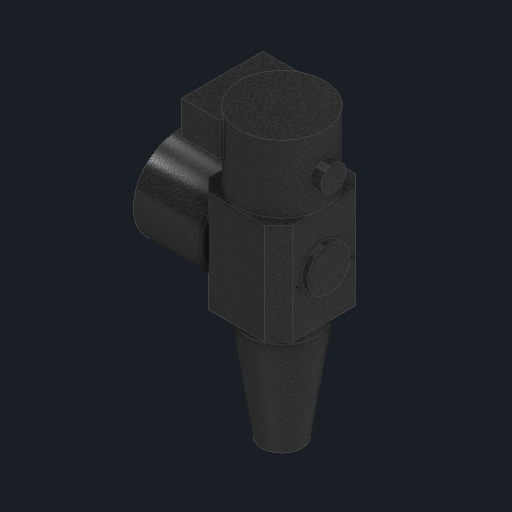
# Autodesk Inventor part: dec_housing
Saved by Autodesk Inventor 2027.1 (Build 311270010, 270A)
## iProperties
Created: 2026-11-03
Part Number: dec_housing
Material: Generic
Description: CG-5 RA shaft collar + Dec axis housing + counterweight cone (estimated)
Document SubType Name: Modeling
Designer: Claude (from photos)
Density: 1 g/cm^3
Appearance: Black Cast
Author: alexg
Autodesk Inventor part; units mm, degrees
ref_plane "Work Plane1" through (95, 0, 0) normal (1, 0, 0) x (0, 1, 0)
sketch "RA collar sketch" plane through (95, 0, 0) normal (1, 0, 0) x (0, 1, 0)
  circle A0 centre (0, 0) radius 40
  constraints: 1 centre point
extrude "RA collar" add sketch "RA collar sketch" along normal blind 60
ref_plane "Work Plane2" through (0, -45, 0) normal (0, 1, 0) x (-1, 0, 0)
sketch "Dec junction sketch" plane through (0, -45, 0) normal (0, 1, 0) x (-1, 0, 0)
  line L0 (-162, -40) -> (-212, -40)
  line L1 (-212, -40) -> (-224, -28)
  line L2 (-224, -28) -> (-224, 28)
  line L3 (-224, 28) -> (-212, 40)
  line L4 (-212, 40) -> (-162, 40)
  line L5 (-162, 40) -> (-150, 28)
  line L6 (-150, 28) -> (-150, -28)
  line L7 (-150, -28) -> (-162, -40)
  constraints: 16 end point
extrude "Dec junction" add sketch "Dec junction sketch" along normal blind 90
ref_plane "Work Plane3" through (0, 45, 0) normal (0, 1, 0) x (-1, 0, 0)
sketch "Dec housing sketch" plane through (0, 45, 0) normal (0, 1, 0) x (-1, 0, 0)
  circle A0 centre (-187, 0) radius 38
  constraints: 1 centre point
extrude "Dec housing" add sketch "Dec housing sketch" along normal blind 60
ref_plane "Work Plane4" through (0, -45, 0) normal (0, 1, 0) x (-1, 0, 0)
sketch "Dec circle seat sketch" plane through (0, -45, 0) normal (0, 1, 0) x (-1, 0, 0)
  circle A0 centre (-187, 0) radius 31
  constraints: 1 centre point
extrude "Dec circle seat" add sketch "Dec circle seat sketch" against normal blind 12
sketch "Counterweight cone sketch" plane through (0, 0, 0) normal (0, 0, 1) x (1, 0, 0)
  line L0 (187, -57) -> (187, -150)
  line L1 (187, -150) -> (205, -150)
  line L2 (205, -150) -> (219, -57)
  line L3 (219, -57) -> (187, -57)
  constraints: 8 end point
revolve "Counterweight cone" add sketch "Counterweight cone sketch" angle 360 about axis through (187, -57, 0) along (0, -1, 0)
ref_plane "Work Plane5" through (0, -150, 0) normal (0, 1, 0) x (-1, 0, 0)
sketch "Counterweight bar socket sketch" plane through (0, -150, 0) normal (0, 1, 0) x (-1, 0, 0)
  circle A0 centre (-187, 0) radius 9.5
  constraints: 1 centre point
extrude "Counterweight bar socket" cut sketch "Counterweight bar socket sketch" along normal blind 15
ref_plane "Work Plane6" through (224, 0, 0) normal (1, 0, 0) x (0, 1, 0)
sketch "RA end cap sketch" plane through (224, 0, 0) normal (1, 0, 0) x (0, 1, 0)
  circle A0 centre (0, 0) radius 19
  constraints: 1 centre point
extrude "RA end cap" add sketch "RA end cap sketch" along normal blind 5
ref_plane "Work Plane7" through (224, 0, 0) normal (1, 0, 0) x (0, 1, 0)
sketch "End face M5 holes sketch" plane through (224, 0, 0) normal (1, 0, 0) x (0, 1, 0)
  circle A0 centre (-6, 23.5) radius 2.6
  circle A1 centre (-6, -23.5) radius 2.6
  constraints: 2 centre point
extrude "End face M5 holes" cut sketch "End face M5 holes sketch" against normal blind 12
ref_plane "Work Plane8" through (215, 0, 0) normal (1, 0, 0) x (0, 1, 0)
sketch "Dec lock boss sketch" plane through (215, 0, 0) normal (1, 0, 0) x (0, 1, 0)
  circle A0 centre (72, 0) radius 11
  constraints: 1 centre point
extrude "Dec lock boss" add sketch "Dec lock boss sketch" along normal blind 18
ref_plane "Work Plane9" through (0, 72, 0) normal (0, 1, 0) x (-1, 0, 0)
sketch "Dec worm block sketch" plane through (0, 72, 0) normal (0, 1, 0) x (-1, 0, 0)
  line L0 (-134, -36) -> (-168, -36)
  line L1 (-168, -36) -> (-168, 36)
  line L2 (-168, 36) -> (-134, 36)
  line L3 (-134, 36) -> (-134, -36)
  constraints: 8 end point, 2 parallel, 1 horizontal, 1 perpendicular
extrude "Dec worm block" add sketch "Dec worm block sketch" along normal blind 30
body "Solid1"
